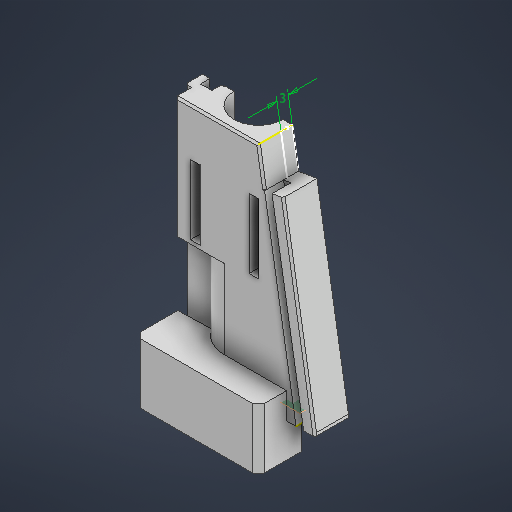
# Autodesk Inventor part: top2
Saved by Autodesk Inventor 2026.3 (Build 303398000, 398)
## iProperties
Created: 2026-07-23
Part Number: top2
Material: Generic
Document SubType Name: Modeling
Designer: BenFr
Density: 1 g/cm^3
Appearance: Default
Author: BenFr
Autodesk Inventor part; units mm, degrees
ref_plane "YZ Plane" through (0, 0, 0) normal (1, 0, 0) x (0, 1, 0)
ref_plane "XZ Plane" through (0, 0, 0) normal (0, 1, 0) x (-1, 0, 0)
ref_plane "XY Plane" through (0, 0, 0) normal (0, 0, 1) x (1, 0, 0)
sketch "Sketch1" plane through (0, 0, 0) normal (0, 1, 0) x (-1, 0, 0)
  line L0 (-10, 0) -> (0, 0)
  circle A0 centre (0, 0) radius 9
  circle A1 centre (0, 0) radius 6.5
  line L1 (0, 0) -> (9, 0)
  point P0 (6.5, 0)
  point P1 (-9, 0)
  point P2 (-6.5, 0)
  dimension "d1" = 18
  dimension "d0" = 10
  dimension "d2" = 13
  constraints: 4 end point, 2 coincident, 2 horizontal, 1 centre point, 3 other
  measures "d0" distance of L0.start L0.end
  measures "d2" diameter of A1
extrude "Extrusion1" add sketch "Sketch1" along normal blind 60 contours A0 L1 A1 L0 picked at (-3.9988, 7.0571)
sketch "Sketch2" plane through (9, 0, 0) normal (0, 0, -1) x (-1, 0, 0)
  line L0 (0, 60) -> (-10, 0)
  line L1 (-10, 0) -> (0, 0)
  line L2 (0, 0) -> (0, 60)
  line L3 (0, 0) -> (0, 60) projected
  point P0 (9, 0)
  dimension "d5" = 10
  constraints: 6 end point, 2 collinear, 1 horizontal, 1 perpendicular
  measures "d5" distance of L0.end L1.end
extrude "Extrusion2" add sketch "Sketch2" against normal blind 9
sketch "Sketch3" plane through (9, 60, 9) normal (0.9863939, 0.164399, 0) x (0, 0, -1)
  line L0 (9, -60.8276) -> (6, -60.8276)
  line L1 (6, -60.8276) -> (6, 0)
  line L2 (6, 0) -> (9, 0)
  line L3 (9, 0) -> (9, -60.8276)
  line L4 (9, 0) -> (0, 0) projected
  line L5 (9, -60.8276) -> (0, -60.8276) projected
  point P0 (9, -57.704)
  point P1 (7.5, 0)
  point P2 (4.5, -60.8276)
  dimension "d8" = 3
  constraints: 8 end point, 3 point on line, 2 midpoint, 2 parallel, 1 horizontal, 1 perpendicular
  measures "d8" distance of L1.end L2.end
extrude "Extrusion3" add sketch "Sketch3" along normal blind 5
sketch "Sketch4" plane through (19, 0, 3) normal (0, 0, 1) x (0.9863939, 0.164399, 0)
  line L0 (0, 60.8276) -> (5, 60.8276) projected
  line L1 (5, 60.8276) -> (2, 60.8276)
  line L2 (2, 60.8276) -> (2, 0)
  line L3 (2, 0) -> (5, 0)
  line L4 (5, 0) -> (5, 60.8276)
  line L5 (0, 0) -> (5, 0) projected
  point P0 (-18.7415, 3.1236)
  point P1 (2, 60.8276)
  dimension "d11" = 3
  constraints: 8 end point, 2 parallel, 1 collinear, 1 horizontal, 1 perpendicular
  measures "d11" distance of L3.end L2.end
extrude "Extrusion4" add sketch "Sketch4" along normal blind 6
sketch "Sketch5" plane through (9, 0, 9) normal (0, 0, 1) x (1, 0, 0)
  line L0 (0, 60) -> (-18, 60) projected
  line L1 (0, 0) -> (-9, 0)
  line L2 (-9, 0) -> (-9, 60)
  line L3 (-9, 60) -> (0, 60)
  line L4 (0, 60) -> (0, 0)
  line L5 (0, 60) -> (0, 0) projected
  point P0 (-9, 0)
  constraints: 8 end point, 2 parallel, 1 collinear, 1 horizontal, 1 midpoint, 1 perpendicular
extrude "Extrusion5" add sketch "Sketch5" against normal up to surface round surface about axis through (0, 0, 0) along (0, 1, 0) radius 9 far side no
ref_plane "Work Plane1" through (0, 5, 0) normal (0, -1, 0) x (1, 0, 0)
sketch "Sketch6" plane through (0, 5, 0) normal (0, -1, 0) x (1, 0, 0)
  circle A0 centre (0, 0) radius 7.75
  dimension "d17" = 15.5
  constraints: 1 centre point, 1 coincident
  measures "d17" diameter of A0
extrude "Extrusion6" cut sketch "Sketch6" against normal blind 3
pattern_linear "Rectangular Pattern1" count 3 spacing 10 along (0, 1, 0) of "Extrusion6"
sketch "Sketch7" plane through (19, 0, 0) normal (0, 0, -1) x (-1, 0, 0)
  line L0 (10, 60) -> (19, 60) projected
  line L1 (0, 0) -> (10, 60) projected
  line L2 (10, 60) -> (0, 0)
  line L3 (19, 0) -> (0, 0) projected
  line L4 (1.1805, 1) -> (6, 1)
  line L5 (6, 1) -> (6, 29.9172)
  line L6 (6, 29.9172) -> (1.1805, 1)
  line L7 (0, 0) -> (12.5, 0) projected
  line L8 (19, -12.1644) -> (19, 72.9864) projected
  line L9 (10, 60) -> (10, 0)
  line L10 (0, 0) -> (-4.932, 0.822) projected
  line L11 (0, 0) -> (10, 0)
  point P0 (5, 0)
  dimension "d27" = 4
  dimension "d28" = 1
  dimension "d29" = 1
  constraints: 12 end point, 2 collinear, 2 parallel, 2 perpendicular, 1 horizontal, 1 midpoint, 1 point on line
  measures "d27" distance between parallel lines of L9 L5
  measures "d28" distance from line of point (5, 0) L4
  measures "d29" distance between parallel lines of L1 L6
sketch "Sketch8" plane through (0, 0, 0) normal (0, -1, 0) x (1, 0, 0)
  line L0 (19, 0) -> (19, 3) projected
  line L1 (20.9728, 9) -> (23.932, 9) projected
  line L2 (19, 0) -> (23.932, 0)
  line L3 (23.932, 0) -> (23.932, 9)
  line L4 (23.932, 9) -> (19, 9)
  line L5 (19, 9) -> (19, 0)
  point P0 (0, 0)
  constraints: 8 end point, 2 parallel, 1 horizontal, 1 perpendicular
extrude "Extrusion7" add sketch "Sketch8" along normal up to surface surface through (19, 0, 3) normal (0.164399, -0.9863939, 0)
sketch "Sketch9" plane through (19, 0, 9) normal (0, 0, 1) x (0.9863939, 0.164399, 0)
  line L0 (2, 0) -> (0, 0)
  line L1 (0, 0) -> (0, -4.987)
  line L2 (0, -4.987) -> (2, -4.987)
  line L3 (2, -4.987) -> (2, 0)
  line L4 (0, 0) -> (0, 60.8276) projected
  point P0 (-18.7415, 3.1236)
  constraints: 8 end point, 2 parallel, 1 collinear, 1 horizontal, 1 perpendicular
extrude "Extrusion8" cut sketch "Sketch9" against normal blind 5.5
extrude "Extrusion9" add sketch "Sketch7" along normal blind 5 contours L6 L5 L4
mirror "Mirror1" about plane through (0, 0, 0) normal (0, 0, 1) remove original yes
chamfer "Chamfer1" distance 3 angle 45 1 edges at (13, 29.9172, 2.5)
sketch "Sketch10" plane through (0, 0, 0) normal (0, -1, 0) x (1, 0, 0)
  point P0 (0, 0)
sketch "Sketch11" plane through (0, 0, 0) normal (0, -1, 0) x (1, 0, 0)
  line L0 (-6.5, 0) -> (-9, 0) projected
  line L1 (-9.6353, -0.2647) -> (-12.6353, -0.2647)
  line L2 (-12.6353, -0.2647) -> (-12.6353, -2.7647)
  line L3 (-12.6353, -2.7647) -> (-9.6353, -2.7647)
  line L4 (-9.6353, -2.7647) -> (-9.6353, -0.2647)
  line L5 (-14.6353, -0.2647) -> (-9.6353, -0.2647)
  line L6 (-9.6353, -0.2647) -> (-9.6353, -4.7647)
  line L7 (-9.6353, -4.7647) -> (-14.6353, -4.7647)
  line L8 (-14.6353, -4.7647) -> (-14.6353, -0.2647)
  line L9 (-9.6353, -4.7647) -> (-7.6353, -4.7647)
  line L10 (-9.6353, -4.7647) -> (-7.6353, -4.7647)
  line L11 (-7.6353, -4.7647) -> (-7.6353, -4.7647)
  arc A0 (-9, 0) -> (0, -9) centre (0, 0) ccw projected
  line L12 (-9.6353, -0.2647) -> (-8.5353, -0.2647)
  line L13 (-8.5353, -0.2647) -> (-8.5353, -2.7647)
  line L14 (-8.5353, -2.7647) -> (-9.6353, -2.7647)
  line L15 (-9.6353, -2.7647) -> (-9.6353, -0.2647)
  line L16 (-9.6353, -2.7647) -> (-7.6353, -2.7647)
  line L17 (-7.6353, -2.7647) -> (-7.6353, -4.7647)
  line L18 (-7.6353, -4.7647) -> (-9.6353, -4.7647)
  line L19 (-9.6353, -4.7647) -> (-9.6353, -2.7647)
  point P0 (-12.6353, -0.2647)
  point P1 (-8.5648, -2.7647)
  point P2 (-8.9961, -0.2647)
  point P3 (-8.6353, -2.5361)
  dimension "d35" = 3
  dimension "d36" = 2.5
  dimension "d37" = 2
  dimension "d38" = 2
  dimension "d104" = 1.1
  dimension "d105" = 2
  dimension "d106" = 0
  constraints: 38 end point, 9 equal length, 6 horizontal, 4 perpendicular, 2 point on line, 2 other
  measures "d35" distance of L3.end L2.end
  measures "d36" distance of L2.end L1.end
  measures "d37" distance between parallel lines of L8 L2
  measures "d38" distance between parallel lines of L3 L7
  measures "d104" distance of L1.start L12.end
  measures "d105" distance of L6.end L9.end
  measures "d106" distance of L9.end L11.end
extrude "Extrusion10" add sketch "Sketch11" against normal blind 60 contours L12 A0 L14 L4 | L2 L3 L6 L7 L8 L5 | L14 A0 L9 L6 | L12 L13 L14 A0
mirror "Mirror2" about plane through (0, 0, 0) normal (0, 0, 1) remove original yes
sketch "Sketch12" plane through (17.8195, 1, -5) normal (0, 0, -1) x (-1, 0, 0)
  line L0 (-0.5312, -0.45) -> (5.7695, -0.45)
  line L1 (5.7695, 37.3545) -> (-0.5312, -0.45)
  line L2 (-1.1805, -1) -> (8.8195, 59) projected
  line L3 (-6.1124, -1) -> (11.3195, -1) projected
  line L4 (5.7695, 37.3545) -> (5.7695, -0.45)
  line L5 (8.8195, 59) -> (8.8195, 0.6295)
  line L6 (5.3237, 34.6794) -> (5.7695, 34.6794)
  point P0 (17.8195, -1)
  dimension "d101" = 0.55
  dimension "d102" = 3.05
  dimension "d103" = 0.55
  constraints: 10 end point, 2 point on line, 2 vertical, 1 horizontal, 1 perpendicular
  measures "d101" distance between parallel lines of L3 L0
  measures "d102" distance between parallel lines of L5 L4
  measures "d103" distance between parallel lines of L2 L1
extrude "Extrusion11" cut sketch "Sketch12" against normal blind 10 contours L1 L6 L4 L0
chamfer "Chamfer2" [suppressed]
sketch "Sketch18" plane through (0, 0, 0) normal (0, -1, 0) x (1, 0, 0)
  line L0 (0, 0) -> (15, 0)
  line L1 (15, 0) -> (15, 15)
  line L2 (15, 15) -> (0, 15)
  line L3 (0, 15) -> (0, 0)
  line L4 (0, 0) -> (-15, 0)
  line L5 (-15, 0) -> (-15, 15)
  line L6 (-15, 15) -> (0, 15)
  line L7 (0, 15) -> (0, 0)
  line L8 (0, 0) -> (16.5, 0)
  line L9 (16.5, 0) -> (16.5, 16.5)
  line L10 (16.5, 16.5) -> (0, 16.5)
  line L11 (0, 16.5) -> (0, 0)
  line L12 (0, 0) -> (-16.5, 0)
  line L13 (-16.5, 0) -> (-16.5, 16.5)
  line L14 (-16.5, 16.5) -> (0, 16.5)
  line L15 (0, 16.5) -> (0, 0)
  line L16 (-16.5, 0) -> (16.5, 0)
  line L17 (16.5, 0) -> (16.5, 5)
  line L18 (16.5, 5) -> (-16.5, 5)
  line L19 (-16.5, 5) -> (-16.5, 0)
  point P0 (0, 16.5)
  point P1 (-15, 0)
  point P2 (0, 15)
  point P3 (15, 0)
  point P4 (-16.5, 5)
  point P5 (-15, 5)
  point P6 (15, 5)
  dimension "d92" = 1.5
  dimension "d93" = 30
  dimension "d94" = 1.5
  dimension "d95" = 1.5
  dimension "d96" = 15
  dimension "d97" = 5
  constraints: 40 end point, 10 parallel, 5 horizontal, 5 perpendicular, 3 point on line, 1 other
  measures "d92" distance between parallel lines of L14 L6
  measures "d93" distance between parallel lines of L5 L1
  measures "d94" distance between parallel lines of L13 L5
  measures "d95" distance between parallel lines of L1 L9
  measures "d96" distance between parallel lines of L4 L6
  measures "d97" distance of L17.end L16.end
extrude "Extrusion16" add sketch "Sketch18" along normal blind 9 and the other way blind 5 contours L1 L2 L11 L10 L9 L18 | L6 L5 L18 L13 L14 L11
sketch "Sketch17" plane through (0, 25, 0) normal (0, 1, 0) x (1, 0, 0)
  circle A0 centre (0, 0) radius 8.25
  dimension "d67" = 16.5
  constraints: 1 centre point, 1 coincident
  measures "d67" diameter of A0
extrude "Extrusion15" cut sketch "Sketch17" along normal blind 3
sketch "Sketch20" plane through (0, 60, 9) normal (0, 1, 0) x (1, 0, 0)
  line L0 (0, 0) -> (-13, 0)
  line L1 (-13, 0) -> (-13, 2.3536)
  line L2 (-13, 2.3536) -> (0, 2.3536)
  line L3 (0, 2.3536) -> (0, 0)
  line L4 (-13, 2.3536) -> (-6.0091, 2.3536)
  line L5 (-6.0091, 2.3536) -> (-6.0091, 4.9939)
  line L6 (-6.0091, 4.9939) -> (-13, 4.9939)
  line L7 (-13, 4.9939) -> (-13, 2.3536)
  point P0 (0, 9)
  dimension "d80" = 13
  constraints: 16 end point, 4 parallel, 2 horizontal, 2 perpendicular
  measures "d80" distance of L0.start L0.end
extrude "Extrusion18" add sketch "Sketch20" against normal blind 32
sketch "Sketch19" plane through (-6.5, 60, 0) normal (0, 0, -1) x (-1, 0, 0)
  line L0 (0, -31) -> (2.6, -31)
  line L1 (2.6, -31) -> (2.6, -12.5)
  line L2 (2.6, -12.5) -> (0, -12.5)
  line L3 (0, -12.5) -> (0, -31)
  line L4 (-13, -31) -> (-15.6, -31)
  line L5 (-15.6, -31) -> (-15.6, -12.5)
  line L6 (-15.6, -12.5) -> (-13, -12.5)
  line L7 (-13, -12.5) -> (-13, -31)
  line L8 (-6.5, -60) -> (-6.5, 0) projected
  line L9 (0, -32) -> (1.75, -32) projected
  point P0 (1.3, -31)
  point P1 (0.875, -32)
  dimension "d74" = 6.5
  dimension "d75" = 2.6
  dimension "d90" = 1
  dimension "d91" = 18.5
  constraints: 16 end point, 4 parallel, 2 horizontal, 2 midpoint, 2 perpendicular, 2 point on line, 2 other
  measures "d74" distance between parallel lines of L8 L7
  measures "d75" distance of L1.end L2.end
  measures "d90" vertical distance of point (1.3, -31) point (0.875, -32)
  measures "d91" distance of L0.end L1.end
extrude "Extrusion17" cut sketch "Sketch19" against normal through all
sketch "Sketch21" plane through (-12.6353, 0, 0.2647) normal (0, 0, -1) x (-1, 0, 0)
  line L0 (0, 0) -> (0, 60) projected
  line L1 (0, 0) -> (1, 0)
  line L2 (1, 0) -> (1, 58)
  line L3 (1, 58) -> (0, 58)
  line L4 (0, 58) -> (0, 0)
  line L5 (2, 60) -> (0, 60) projected
  point P0 (-12.6353, 0)
  point P1 (0, 58)
  dimension "d81" = 1
  dimension "d82" = 2
  constraints: 8 end point, 2 parallel, 1 horizontal, 1 perpendicular
  measures "d81" distance between parallel lines of L0 L2
  measures "d82" distance between parallel lines of L5 L3
extrude "Extrusion19" cut sketch "Sketch21" against normal blind 2.5
sketch "Sketch22" plane through (13.932, 60.822, 9) normal (-0.164399, 0.9863939, 0) x (0.9863939, 0.164399, 0)
  line L0 (0, 9) -> (0, 0) projected
  line L1 (-0.1351, 9) -> (-17.3299, 9) projected
  line L2 (0, 0) -> (-5.0061, 0)
  line L3 (-5.0061, 0) -> (-5.0061, 9)
  line L4 (-5.0061, 9) -> (0, 9)
  line L5 (0, 9) -> (0, 0)
  point P0 (-23.7415, 9)
  point P1 (-17.0833, 9)
  point P2 (0, 9)
  point P3 (-0.1351, 9)
  constraints: 8 end point, 2 parallel, 1 horizontal, 1 perpendicular, 1 point on line
extrude "Extrusion20" cut sketch "Sketch22" against normal blind 10
chamfer "Chamfer3" distance 0.5 angle 45 5 edges at (19.7541, 25.889, 9) (-2.0031, 60, 9) (9.816, 55.0665, 9) (-13, 44, 9) (-14.6353, 30, 4.7647)
sketch "Sketch24" plane through (19, 0, 9) normal (0.9863939, 0.164399, 0) x (0, 0, -1)
  line L0 (6, 0) -> (6, 50.8276) projected
  line L1 (6, 50.8276) -> (5, 50.8276)
  line L2 (5, 50.8276) -> (8.7167, 0)
  line L3 (8.7167, 0) -> (6, 50.8276)
  point P0 (9, 3.1236)
  dimension "d109" = 1
  constraints: 6 end point, 1 horizontal
  measures "d109" distance of L0.end L1.end
extrude "Extrusion22" add sketch "Sketch24" along normal up to surface (2 mm away)
sketch "Sketch25" plane through (0, 5, 0) normal (0, 1, 0) x (1, 0, 0)
  arc A0 (-7.6353, -4.7647) -> (-0.0005, -9) centre (0.1948, 0.3512) ccw
  line L0 (15, -9) -> (16.5, -9) projected
  line L1 (-0.0005, -9) -> (16.5, -9)
  line L2 (-16.5, -16.5) -> (16.5, -16.5) projected
  line L3 (16.5, -9) -> (16.5, -16.5)
  line L4 (16.5, -16.5) -> (-16.4467, -16.5)
  line L5 (-16.4467, -16.5) -> (-16.4934, -4.9934)
  line L6 (-16.4934, -4.9934) -> (-7.6353, -4.7647)
  point P0 (0, 0)
  constraints: 10 end point, 2 perpendicular, 2 point on circle, 1 centre point, 1 horizontal
extrude "Extrusion23" add sketch "Sketch25" along normal blind 2
chamfer "Chamfer4" distance 1.5 angle 45 2 edges at (16.5, -1, 16.5) (-16.5, -2, 16.5)
equation "\"d6\" = 0.5 * d1"
body "Solid1"
